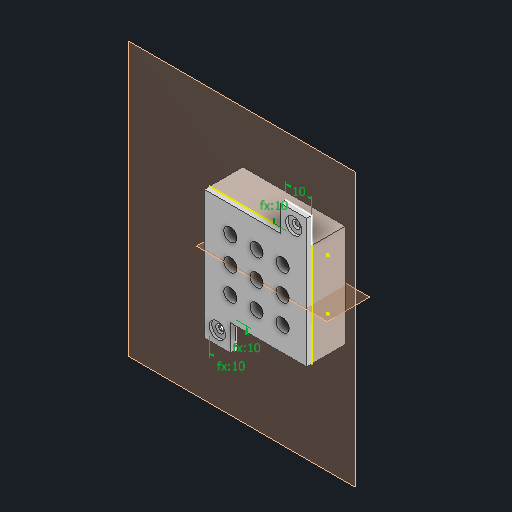
# Autodesk Inventor part: scd40holdertop
Saved by Autodesk Inventor 2026.1 (Build 301233020, 233B)
## iProperties
Created: 2026-06-04
Part Number: scd40holdertop
Material: Générique
Document SubType Name: Modeling
Designer: matpo
Density: 1 g/cm^3
Appearance: Par défaut
Author: matpo
Autodesk Inventor part; units mm, degrees
ref_plane "YZ Plane" through (0, 0, 0) normal (1, 0, 0) x (0, 1, 0)
ref_plane "Plan de construction1" through (0, 0, 0) normal (0, 0, 1) x (1, 0, 0)
sketch "Esquisse1" plane through (0, 0, 0) normal (0, 0, 1) x (1, 0, 0)
  line L0 (-8.7, 17.2) -> (-43.1, 17.2) projected
  line L1 (-25.9, 10) -> (-15.9, 10) projected
  line L2 (-15.9, 10) -> (-15.9, -10) projected
  line L3 (-15.9, -10) -> (-35.9, -10) projected
  line L4 (-35.9, -10) -> (-35.9, 25) projected
  line L5 (-25.9, 25) -> (-25.9, 10) projected
  line L6 (6.3, -35.9011) -> (6.3, 36.618) projected
  arc A0 (-2.4, 47.5) -> (6.3, 36.618) centre (0, 40.5) ccw projected
  line L7 (-62.5, 47.5) -> (-2.4, 47.5) projected
  arc A1 (-62.5, 47.5) -> (-72.5, 37.5) centre (-62.5, 37.5) ccw projected
  line L8 (-72.5, 2.4) -> (-72.5, 37.5) projected
  arc A2 (-72.5, -2.4) -> (-72.5, 2.4) centre (-65.5, 0) ccw projected
  line L9 (-72.5, -37.5) -> (-72.5, -2.4) projected
  arc A3 (-72.5, -37.5) -> (-62.5, -47.5) centre (-62.5, -37.5) ccw projected
  line L10 (-3.4409, -47.5) -> (-62.5, -47.5) projected
  arc A4 (6.3, -35.9011) -> (-3.4409, -47.5) centre (0, -40.5) ccw projected
  line L11 (-43.1, -17.2) -> (-8.7, 17.2) construction
  line L12 (-8.7, -17.2) -> (-43.1, 17.2) construction
  line L13 (-8.3, -17.6) -> (-43.5, -17.6)
  line L14 (-43.5, -17.6) -> (-43.5, 17.6)
  line L15 (-43.5, 17.6) -> (-8.3, 17.6)
  line L16 (-8.3, 17.6) -> (-8.3, -17.6)
  line L17 (-8.3, -17.6) -> (-43.5, 17.6) construction
  line L18 (-43.5, -17.6) -> (-8.3, 17.6) construction
  line L19 (-6.3, 19.6) -> (-45.5, 19.6)
  line L20 (-45.5, 19.6) -> (-45.5, -19.6)
  line L21 (-45.5, -19.6) -> (-6.3, -19.6)
  line L22 (-6.3, -19.6) -> (-6.3, 19.6)
  circle A5 centre (-40.5, -24.6) radius 2.1 projected
  circle A6 centre (-11.3, 24.6) radius 2.1 projected
  line L23 (-35.9, 25) -> (-25.9, 25) projected
  point P0 (0, 0)
  point P1 (-25.9, 0)
  dimension "d0" = 0.4
  dimension "d2" = 2
  constraints: 24 end point, 4 parallel, 3 midpoint, 3 perpendicular, 1 horizontal, 3 other
  measures "d0" distance between parallel lines of L0 L15
  measures "d2" distance between parallel lines of L15 L19
ref_plane "Plan de construction2" through (-46.061, -20.1431, -13) normal (0, 0, 1) x (1, 0, 0)
extrude "Extrusion1" add sketch "Esquisse1" against normal blind 12.8 contours L5 L1 L2 L3 L4 L0 | L0 L4 L15 L5 | L5 L15 L16 L13 L14 L4 L3 L2 L1 | L15 L4 L19 L5 | L5 L19 L22 L21 L20 L4 L15 L14 L13 L16
sketch "Esquisse2" plane through (0, 0, -12.8) normal (0, 0, -1) x (-1, 0, 0)
  line L0 (43.5, 17.6) -> (8.3, 17.6) projected
  line L1 (43.5, -17.6) -> (43.5, 17.6) projected
  line L2 (8.3, -17.6) -> (43.5, -17.6) projected
  line L3 (8.3, 17.6) -> (8.3, -17.6) projected
  point P0 (0, 0)
extrude "Extrusion2" cut sketch "Esquisse2" against normal blind 10.9
sketch "Esquisse4" plane through (0, 0, 0) normal (0, 0, 1) x (1, 0, 0)
  line L0 (-45.5, 19.6) -> (-45.5, -19.6) projected
  line L1 (-45.5, -19.6) -> (-6.3, -19.6) projected
  line L2 (-6.3, -19.6) -> (-6.3, 19.6) projected
  line L3 (-6.3, 19.6) -> (-45.5, 19.6) projected
  line L4 (-6.3, 19.6) -> (-16.3, 19.6)
  line L5 (-16.3, 19.6) -> (-16.3, 29.6)
  line L6 (-16.3, 29.6) -> (-6.3, 29.6)
  line L7 (-6.3, 29.6) -> (-6.3, 19.6)
  line L8 (-45.5, -19.6) -> (-35.5, -19.6)
  line L9 (-35.5, -19.6) -> (-35.5, -29.6)
  line L10 (-35.5, -29.6) -> (-45.5, -29.6)
  line L11 (-45.5, -29.6) -> (-45.5, -19.6)
  line L12 (-6.3, 29.6) -> (-16.3, 19.6) construction
  line L13 (-6.3, 19.6) -> (-16.3, 29.6) construction
  line L14 (-35.5, -19.6) -> (-45.5, -29.6) construction
  line L15 (-35.5, -29.6) -> (-45.5, -19.6) construction
  point P0 (0, 0)
  point P1 (-35.5, -19.6)
  point P2 (-40.5, -24.6)
  point P3 (-11.3, 24.6)
  dimension "d13" = 10
  dimension "d14" = 10
  dimension "d15" = 10
  dimension "d16" = 10
  constraints: 24 end point, 4 parallel, 3 perpendicular, 2 horizontal, 2 midpoint, 1 point on line
  measures "d13" distance of L5.end L6.end
  measures "d14" distance of L4.end L5.end
  measures "d15" distance of L9.end L10.end
  measures "d16" distance of L8.end L9.end
extrude "Extrusion4" add sketch "Esquisse4" along normal blind 2
sketch "Esquisse7" plane through (0, 0, 2) normal (0, 0, 1) x (1, 0, 0)
  point P0 (0, 0)
  point P1 (-11.3, 24.6)
  point P2 (-40.5, -24.6)
hole "Perçage2" at (-11.3, 24.6, 2) at (-40.5, -24.6, 2) direction (0, 0, -1) diameter 3.2 depth 8 counterbore diameter 6.2 counterbore depth 1
sketch "Esquisse8" plane through (0, 0, 2) normal (0, 0, 1) x (1, 0, 0)
  circle A0 centre (-40.5, -24.6) radius 3.1 projected
  circle A1 centre (-11.3, 24.6) radius 3.1 projected
  line L0 (-45.5, -29.6) -> (-35.5, -29.6) projected
  line L1 (-35.5, -29.6) -> (-35.5, -19.6) projected
  line L2 (-35.5, -19.6) -> (-6.3, -19.6) projected
  line L3 (-6.3, -19.6) -> (-6.3, 29.6) projected
  line L4 (-6.3, 29.6) -> (-16.3, 29.6) projected
  line L5 (-16.3, 29.6) -> (-16.3, 19.6) projected
  line L6 (-16.3, 19.6) -> (-45.5, 19.6) projected
  line L7 (-45.5, 19.6) -> (-45.5, -29.6) projected
  circle A2 centre (-35.5, 9.6) radius 2.5
  circle A3 centre (-25.5, 9.6) radius 2.5
  circle A4 centre (-15.5, 9.6) radius 2.5
  circle A5 centre (-35.5, -0.4) radius 2.5
  circle A6 centre (-25.5, -0.4) radius 2.5
  circle A7 centre (-15.5, -0.4) radius 2.5
  circle A8 centre (-35.5, -10.4) radius 2.5
  circle A9 centre (-25.5, -10.4) radius 2.5
  circle A10 centre (-15.5, -10.4) radius 2.5
  point P0 (0, 0)
  dimension "d33" = 5
  dimension "d34" = 10
  dimension "d35" = 10
  dimension "d38" = 10
  dimension "d41" = 10
  constraints: 9 centre point, 1 horizontal, 1 vertical, 16 other
  measures "d33" diameter of A2
  measures "d34" distance from line of L6 A2.centre
  measures "d35" distance from line of L7 A2.centre
  measures "d38" distance of A2.centre A3.centre
  measures "d41" distance of A2.centre A5.centre
extrude "Extrusion5" cut sketch "Esquisse8" against normal through all contours A2 | A3 | A4 | A5 | A6 | A7 | A8 | A9 | A10
sketch "Esquisse9" plane through (0, 0, -1.9) normal (0, 0, -1) x (-1, 0, 0)
  line L0 (43.1, 17.2) -> (43.1, -17.2) projected
  line L1 (42.1, -16.2) -> (42.1, 16.2)
  line L2 (42.1, 16.2) -> (9.7, 16.2)
  line L3 (9.7, 16.2) -> (9.7, -16.2)
  line L4 (9.7, -16.2) -> (42.1, -16.2)
  point P0 (0, 0)
  dimension "d46" = 1
  constraints: 8 end point
  measures "d46" distance between parallel lines of L0 L1
ref_plane "Plan de construction3" through (-43.5, 0, -12.8) normal (0, 1, 0) x (1, 0, 0)
sketch "Esquisse10" plane through (-43.5, 0, -12.8) normal (0, 1, 0) x (1, 0, 0)
  line L0 (1, -11.3) -> (1.8, -11.3)
  line L1 (1.8, -11.3) -> (1.8, -10.5)
  line L2 (1.8, -10.5) -> (1, -10.5)
  line L3 (1, -10.5) -> (1, -11.3)
  line L4 (1, -11.3) -> (1.8, -10.5) construction
  line L5 (1.8, -11.3) -> (1, -10.5) construction
  point P0 (43.5, -12.8)
  point P1 (1.4, -10.9)
  point P2 (1.4, -10.9)
  point P3 (1.4, -10.9)
  dimension "d47" = 0.8
  dimension "d48" = 0.8
  constraints: 12 end point, 2 midpoint, 2 parallel, 1 horizontal, 1 perpendicular
  measures "d47" distance of L2.end L1.end
  measures "d48" distance of L1.end L0.end
sweep "Balayage1" cut profiles "Esquisse10" path "Esquisse9" path curves L1 L2 L3 L4
sketch "Esquisse11" plane through (-45.5, 19.6, -12.8) normal (0, 1, 0) x (1, 0, 0)
  point P0 (45.5, -12.8)
ref_plane "Plan de construction4" through (-43.3848, 17.2, -13.8908) normal (0, 1, 0) x (0, 0, 1)
equation "\"d14\" = d13"
equation "\"d15\" = d13"
equation "\"d16\" = d13"
